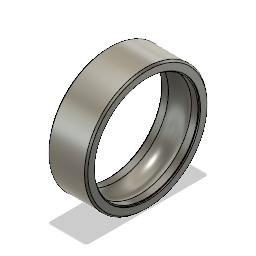
Assembled Bearing 8x22x7 v15 (Autodesk Fusion 360 archive; units mm, degrees)
design "Yttre ringen"
Autodesk Fusion 360 part; units mm, degrees
sketch "Sketch1" plane through (0, 0, 0) normal (0, 0, 1) x (1, 0, 0)
  line L0 (-3.5, 11) -> (3.5, 11)
  line L1 (3.5, 11) -> (3.5, 9.5)
  line L2 (-3.5, 9.5) -> (-3.5, 11)
  line L3 (0, 0) -> (0, 23.7231) construction
  line L4 (-3.25, 9.5) -> (-3.5, 9.5)
  line L5 (-3.25, 9.5) -> (-3.25, 9.3)
  line L6 (3.5, 9.5) -> (3.25, 9.5)
  line L7 (3.25, 9.5) -> (3.25, 9.3)
  line L8 (3.5, 5.34) -> (3.5, 3.94)
  line L9 (3.5, 3.94) -> (-3.5, 3.94)
  line L10 (-3.5, 3.94) -> (-3.5, 5.54)
  line L11 (-3.25, 5.54) -> (-3.25, 5.34)
  line L12 (-3.25, 5.34) -> (-3.5, 5.34)
  line L13 (3.25, 5.54) -> (3.25, 5.34)
  line L14 (3.25, 5.34) -> (3.5, 5.34)
  line L15 (-3.0905, 8.3) -> (3.0905, 8.3)
  line L16 (3.0905, 6.64) -> (-3.0905, 6.64)
  line L17 (-5.3, 7.47) -> (4.8, 7.47) construction
  line L18 (3.25, 9.3) -> (2.0527, 9.3)
  line L19 (-2.0527, 9.3) -> (-3.25, 9.3)
  arc A0 (2.0527, 9.3) -> (-2.0527, 9.3) centre (0, 7.47) ccw
  arc A1 (-1.959, 5.54) -> (1.959, 5.54) centre (0, 7.47) ccw
  line L20 (-3.25, 5.54) -> (-1.959, 5.54)
  line L21 (1.959, 5.54) -> (3.25, 5.54)
  circle A2 centre (0, 7.47) radius 2.75 construction
  arc A3 (-3.0905, 8.3) -> (-3.0905, 6.64) centre (0, 7.47) ccw
  arc A4 (3.0905, 6.64) -> (3.0905, 8.3) centre (0, 7.47) ccw
  dimension "d1" = 7
  dimension "d3" = 0.25
  dimension "d6" = 11
  dimension "d7" = 1.6
  dimension "d8" = 3.94
  dimension "d9" = 1.4
  dimension "d11" = 1
  dimension "d12" = 5.5
  dimension "d13" = 1.7
  dimension "d14" = 0.2
  dimension "d15" = 5.5
  dimension "d16" = 3.2
  dimension "d19" = 3.2
  measures "d6" distance of L3.start L0
  measures "d7" distance of L9 L20
  measures "d8" distance of L3.start L9
  measures "d9" distance of L9 L12
  measures "d11" distance of L15 L18
  measures "d12" diameter of A0
  measures "d13" distance of L0 L19
  measures "d14" distance of L4 L19
  measures "d15" diameter of A2
  measures "d16" radius of A3
  measures "d19" radius of A4
sketch "Sketch2" plane through (0, 0, 0) normal (0, 0, 1) x (1, 0, 0)
revolve "Revolve1" add sketch "Sketch1" angle 360 about axis through (1.75, 0, 0) along (1, 0, 0) contours L0 L1 L2 L4 L5 L6 L7 L18 L19 A0
chamfer "Chamfer1" distance 0.3 angle 45 2 edges at (3.5, -3.9778, 10.2556) (-3.5, -3.9778, 10.2556)
equation "d8 = ( 7.88 / 2 ) * 1 mm"

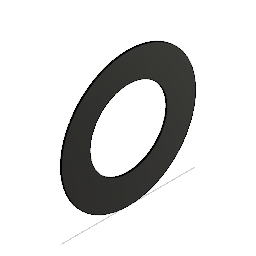
design "Sidoskydd"
Autodesk Fusion 360 part; units mm, degrees
sketch "Sketch1" plane through (0, 0, 0) normal (1, 0, 0) x (0, 0, -1)
  circle A0 centre (0, 0) radius 9.5
  circle A1 centre (0, 0) radius 5.4
  dimension "d1" = 19
  dimension "d2" = 10.8
  measures "d1" diameter of A0
  measures "d2" diameter of A1
extrude "Extrude1" add sketch "Sketch1" along normal blind 0.15
equation "d1 = ( 9.5 * 2 ) * 1 mm"
equation "d2 = ( 5.40 * 2 ) * 1 mm"

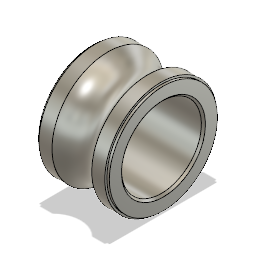
design "Nedre ringen"
Autodesk Fusion 360 part; units mm, degrees
sketch "Sketch1" plane through (0, 0, 0) normal (0, 0, 1) x (1, 0, 0)
  line L0 (-3.5, 11) -> (3.5, 11)
  line L1 (3.5, 11) -> (3.5, 9.5)
  line L2 (-3.5, 9.5) -> (-3.5, 11)
  line L3 (0, 0) -> (0, 23.7231) construction
  line L4 (-3.25, 9.5) -> (-3.5, 9.5)
  line L5 (-3.25, 9.5) -> (-3.25, 9.3)
  line L6 (3.5, 9.5) -> (3.25, 9.5)
  line L7 (3.25, 9.5) -> (3.25, 9.3)
  line L8 (3.5, 5.34) -> (3.5, 3.94)
  line L9 (3.5, 3.94) -> (-3.5, 3.94)
  line L10 (-3.5, 3.94) -> (-3.5, 5.54)
  line L11 (-3.25, 5.54) -> (-3.25, 5.34)
  line L12 (-3.25, 5.34) -> (-3.5, 5.34)
  line L13 (3.25, 5.54) -> (3.25, 5.34)
  line L14 (3.25, 5.34) -> (3.5, 5.34)
  line L15 (-3.0905, 8.3) -> (3.0905, 8.3)
  line L16 (3.0905, 6.64) -> (-3.0905, 6.64)
  line L17 (-5.3, 7.47) -> (4.8, 7.47) construction
  line L18 (3.25, 9.3) -> (2.0527, 9.3)
  line L19 (-2.0527, 9.3) -> (-3.25, 9.3)
  arc A0 (2.0527, 9.3) -> (-2.0527, 9.3) centre (0, 7.47) ccw
  arc A1 (-1.959, 5.54) -> (1.959, 5.54) centre (0, 7.47) ccw
  line L20 (-3.25, 5.54) -> (-1.959, 5.54)
  line L21 (1.959, 5.54) -> (3.25, 5.54)
  circle A2 centre (0, 7.47) radius 2.75 construction
  arc A3 (-3.0905, 8.3) -> (-3.0905, 6.64) centre (0, 7.47) ccw
  arc A4 (3.0905, 6.64) -> (3.0905, 8.3) centre (0, 7.47) ccw
  dimension "d1" = 7
  dimension "d3" = 0.25
  dimension "d6" = 11
  dimension "d7" = 1.6
  dimension "d8" = 3.94
  dimension "d9" = 1.4
  dimension "d11" = 1
  dimension "d12" = 5.5
  dimension "d13" = 1.7
  dimension "d14" = 0.2
  dimension "d15" = 5.5
  dimension "d16" = 3.2
  dimension "d19" = 3.2
  measures "d6" distance of L3.start L0
  measures "d7" distance of L9 L20
  measures "d8" distance of L3.start L9
  measures "d9" distance of L9 L12
  measures "d11" distance of L15 L18
  measures "d12" diameter of A0
  measures "d13" distance of L0 L19
  measures "d14" distance of L4 L19
  measures "d15" diameter of A2
  measures "d16" radius of A3
  measures "d19" radius of A4
sketch "Sketch2" plane through (0, 0, 0) normal (0, 0, 1) x (1, 0, 0)
revolve "Revolve2" add sketch "Sketch1" angle 360 about axis through (1.75, 0, 0) along (1, 0, 0) contours L8 L9 L10 L11 L12 L13 L14 A1 L20 L21
chamfer "Chamfer1" distance 0.2 angle 45 2 edges at (3.5, -1.4248, 3.6734) (-3.5, -1.4248, 3.6734)
equation "d8 = ( 7.88 / 2 ) * 1 mm"

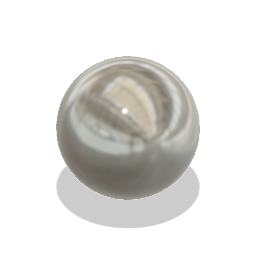
design "Kula"
Autodesk Fusion 360 part; units mm, degrees
sphere "SpherePrimitive1" add diameter 5.5 placed x (1, 0, 0) y (0, 1, 0) z (0, 0, 1) at (0, 0, 0)
